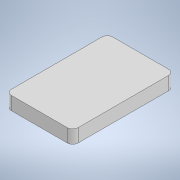
# Autodesk Inventor part: saltea
Saved by Autodesk Inventor 2022.6 (Build 266554000, 554)
## iProperties
Created: 2025-04-23
Part Number: saltea
Material: Generic
Document SubType Name: Modeling
Designer: Dragos Macovei
Density: 1 g/cm^3
Appearance: Default
Author: Dragos Macovei
Autodesk Inventor part; units mm, degrees
ref_plane "YZ Plane" through (0, 0, 0) normal (1, 0, 0) x (0, 1, 0)
ref_plane "XZ Plane" through (0, 0, 0) normal (0, 1, 0) x (-1, 0, 0)
ref_plane "XY Plane" through (0, 0, 0) normal (0, 0, 1) x (1, 0, 0)
sketch "Sketch1" plane through (0, 0, 0) normal (0, 1, 0) x (-1, 0, 0)
  line L0 (100, 0) -> (1150, 0)
  line L1 (1250, 100) -> (1250, 1800)
  line L2 (1150, 1900) -> (100, 1900)
  line L3 (0, 1800) -> (0, 100)
  arc A0 (1250, 1800) -> (1150, 1900) centre (1150, 1800) ccw
  arc A1 (100, 1900) -> (0, 1800) centre (100, 1800) ccw
  arc A2 (0, 100) -> (100, 0) centre (100, 100) ccw
  arc A3 (1150, 0) -> (1250, 100) centre (1150, 100) ccw
  point P0 (0, 0)
  point P1 (1250, 1900)
  point P2 (1250, 0)
  point P3 (0, 1900)
  dimension "d0" = 1250
  dimension "d1" = 1900
  dimension "d2" = 100
  constraints: 8 end point, 8 point on circle, 8 point on line, 8 tangent, 4 centre point, 3 equal radius, 2 parallel, 1 horizontal, 1 perpendicular
  measures "d0" distance of point (0, 1900) point (1250, 1900)
  measures "d1" distance of point (1250, 1900) point (1250, 0)
  measures "d2" radius of A0
extrude "Extrusion1" add sketch "Sketch1" along normal blind 250
body "Solid1"
